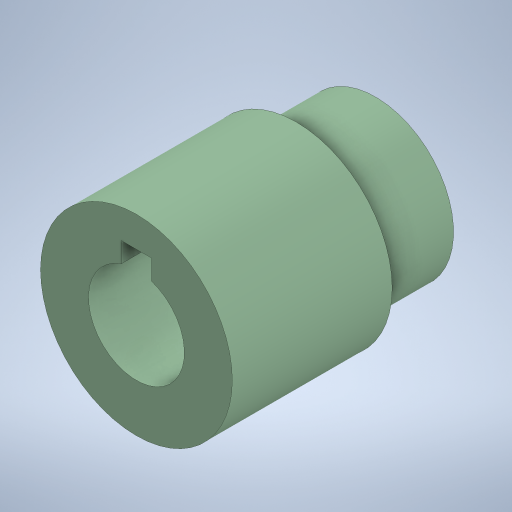
# Autodesk Inventor part: Gear3
Saved by Autodesk Inventor 2023 (Build 270158000, 158)
## iProperties
Created: 2024-05-11
Part Number: Gear3
Material: Generic
Document SubType Name: Modeling
Designer: BenFr
Density: 1 g/cm^3
Appearance: Rubber - Green
Author: BenFr
Autodesk Inventor part; units mm, degrees
ref_plane "YZ Plane" through (0, 0, 0) normal (1, 0, 0) x (0, 1, 0)
ref_plane "XZ Plane" through (0, 0, 0) normal (0, 1, 0) x (-1, 0, 0)
ref_plane "XY Plane" through (0, 0, 0) normal (0, 0, 1) x (1, 0, 0)
sketch "Sketch2" plane through (0, 0, 0) normal (0, 1, 0) x (-1, 0, 0)
  line L0 (0, 0) -> (19.05, 0)
  line L1 (19.05, 0) -> (19.05, -31.75)
  line L2 (0, 0) -> (0, -47.5)
  line L3 (0, -47.5) -> (15.495, -47.5)
  line L4 (15.495, -47.5) -> (15.495, -31.75)
  line L5 (15.495, -31.75) -> (19.05, -31.75)
  line L6 (0, 0) -> (9.525, 0)
  line L7 (9.525, 0) -> (9.525, -47.5)
  dimension "d0" = 19.05
  dimension "d1" = 31.75
  dimension "d2" = 47.5
  dimension "d3" = 15.495
  dimension "d4" = 9.525
  constraints: 16 end point, 4 perpendicular, 2 vertical, 1 horizontal, 1 midpoint, 1 point on line
  measures "d0" distance of L0.start L0.end
  measures "d1" distance of L0.end L1.end
  measures "d2" distance of L0.start L2.end
  measures "d3" distance of L2.end L3.end
  measures "d4" distance of L0.start L6.end
revolve "Revolution1" add sketch "Sketch2" angle 360 about axis through (0, 0, 0) along (0, 0, -1) contours L0 L1 L5 L4 L3 L7
sketch "Sketch3" plane through (0, 0, 0) normal (0, 0, 1) x (1, 0, 0)
  line L0 (-3, 6.025) -> (3, 6.025)
  line L1 (3, 6.025) -> (3, 13.025)
  line L2 (3, 13.025) -> (-3, 13.025)
  line L3 (-3, 13.025) -> (-3, 6.025)
  circle A0 centre (0, 0) radius 9.525 projected
  line L4 (-3, 6.025) -> (3, 13.025) construction
  line L5 (3, 6.025) -> (-3, 13.025) construction
  point P0 (0, 9.525)
  dimension "d6" = 6
  dimension "d7" = 7
  constraints: 12 end point, 2 midpoint, 2 parallel, 1 horizontal, 1 perpendicular, 1 vertical alignment, 1 other
  measures "d6" distance of L2.end L1.end
  measures "d7" distance of L1.end L0.end
extrude "Extrusion1" cut sketch "Sketch3" against normal through all contours L3 A0 L1 L0 | L3 L2 L1 A0 picked at (0.3385, 7.1736)
body "Solid1"
